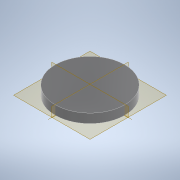
# Autodesk Inventor part: Palm
Saved by Autodesk Inventor 2021 (Build 250183000, 183)
## iProperties
Created: 2026-04-23
Part Number: Palm
Material: Generic
Document SubType Name: Modeling
Designer: Admin
Density: 1 g/cm^3
Appearance: Silicon Nitride - Polished
Author: Admin
Autodesk Inventor part; units mm, degrees
sketch "Sketch1" plane through (0, 0, 0) normal (0, 0, 1) x (1, 0, 0)
  line L0 (-21, 0) -> (-21, 5.5)
  line L1 (-21, 5.5) -> (0, 5.5)
  line L2 (0, 5.5) -> (0, 4)
  line L3 (0, 4) -> (-20, 4)
  line L4 (-20, 4) -> (-20, 1)
  line L5 (-20, 1) -> (-19, 1)
  line L6 (-19, 1) -> (-20, 0)
  line L7 (-20, 0) -> (-21, 0)
  line L8 (0, 6.6) -> (0, -1.1) projected
  line L9 (-25.2, 0) -> (4.2, 0) projected
  point P0 (0, 0)
  dimension "d0" = 21
  dimension "d1" = 20
  dimension "d2" = 3
  dimension "d3" = 1
  dimension "d4" = 1.5
  dimension "d5" = 1
  constraints: 16 end point, 5 perpendicular, 3 point on line, 1 parallel, 1 vertical
  measures "d0" distance of L0.end L1.end
  measures "d1" distance of L2.end L3.end
  measures "d2" distance from line of L3 L4.end
  measures "d3" distance of L4.end L5.end
  measures "d4" distance of L1.end L2.end
  measures "d5" horizontal distance of L5.end L6.end
revolve "Revolution1" add sketch "Sketch1" angle 360 about axis through (0, 5.5, 0) along (0, -1, 0) contours L0 L1 L2 L3 L4 L5 L6 L7
body "Solid1"
